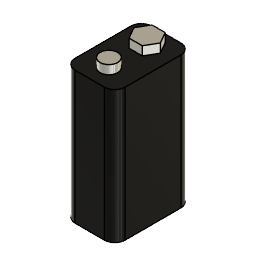
Rover (Autodesk Fusion 360 archive; units mm, degrees)
design "9V_Battery"
Autodesk Fusion 360 part; units mm, degrees
sketch "Skizze1" plane through (0, 0, 0) normal (0, 0, 1) x (1, 0, 0)
  line L0 (8.5, 13) -> (-8.5, 13)
  line L1 (-8.5, 13) -> (-8.5, -13)
  line L2 (-8.5, -13) -> (8.5, -13)
  line L3 (8.5, -13) -> (8.5, 13)
  line L4 (8.5, 13) -> (-8.5, -13) construction
  line L5 (-8.5, 13) -> (8.5, -13) construction
  dimension "d1" = 17
  dimension "d2" = 26
  constraint horizontal L0
  constraint perpendicular L0 L1
  constraint parallel L0 L2
  constraint parallel L1 L3
  constraint coincident L4 origin
  constraint coincident L5 origin
  measures "d1" distance of L0.start L0.end
  measures "d2" distance of L0.start L2.end
extrude "Extrusion1" add sketch "Skizze1" along normal blind 45
sketch "Skizze2" plane through (0, 0, 45) normal (0, 0, 1) x (-1, 0, 0)
  line L0 (-8.5, 13) -> (-8.5, -13)
  line L1 (-8.5, -13) -> (8.5, -13)
  line L2 (8.5, -13) -> (8.5, 13)
  line L3 (8.5, 13) -> (-8.5, 13)
  circle A0 centre (0, -6.5) radius 3 construction
  circle A1 centre (0, 6.5) radius 3
  line L4 (0, 0) -> (-12.8308, 0) construction
  line L5 (2.25, -10.3971) -> (-2.25, -10.3971)
  line L6 (-2.25, -10.3971) -> (-4.5, -6.5)
  line L7 (-4.5, -6.5) -> (-2.25, -2.6029)
  line L8 (-2.25, -2.6029) -> (2.25, -2.6029)
  line L9 (2.25, -2.6029) -> (4.5, -6.5)
  line L10 (4.5, -6.5) -> (2.25, -10.3971)
  circle A2 centre (0, -6.5) radius 4.5 construction
  line L11 (0, 0) -> (0, -16.3032) construction
  dimension "d5" = 13
  dimension "d6" = 6
  dimension "d7" = 9
  constraint coincident L4.start L11.start
  constraint horizontal L4
  constraint symmetric A0 A1 L4
  constraint horizontal L5
  constraint parallel L5 L8
  constraint parallel L6 L9
  constraint equal L5 L6
  constraint equal L5 L10
  constraint equal L9 L10
  constraint equal L8 L9
  constraint parallel L7 L10
  constraint coincident L5.end A2
  constraint coincident L6.end A2
  constraint coincident L7.end A2
  constraint coincident L8.end A2
  constraint coincident L9.end A2
  constraint coincident A0.centre A2.centre
  constraint perpendicular L1 L11
  constraint coincident A0.centre L11
  measures "d5" distance of A0.centre A1.centre
  measures "d6" diameter of A1
  measures "d7" distance of L6.end L9.end
extrude "Extrusion2" add sketch "Skizze2" along normal blind 3 contours A1 | L5 L6 L7 L8 L9 L10
fillet "Abrundung1" radius 3.5 4 edges at (-8.5, -13, 22.5) (-8.5, 13, 22.5) (8.5, 13, 22.5) (8.5, -13, 22.5)

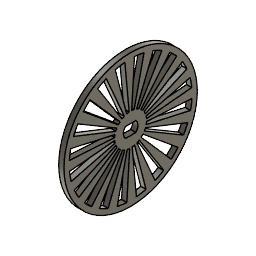
design "Encoder_Wheel_40"
Autodesk Fusion 360 part; units mm, degrees
sketch "Skizze1" plane through (0, 0, 0) normal (1, 0, 0) x (0, 1, 0)
  circle A0 centre (0, 0) radius 25
  circle A1 centre (0, 0) radius 6
  circle A2 centre (0, 0) radius 2.725
  line L0 (-1.9287, 1.925) -> (1.9287, 1.925)
  line L1 (-1.9287, -1.925) -> (1.9287, -1.925)
  line L2 (0, 0) -> (4.9, 0) construction
  circle A3 centre (0, 0) radius 23
  line L3 (-2.1738, 22.897) -> (-0.5671, 5.9731)
  line L4 (0, 0) -> (-0.5671, 5.9731) construction
  line L5 (0, 0) -> (0.5671, 5.9731) construction
  line L6 (0, 0) -> (0, 27) construction
  line L7 (-5.7289, 22.2751) -> (-1.4945, 5.8109)
  line L8 (-9.143, 21.1046) -> (-2.3851, 5.5056)
  line L9 (-12.3319, 19.4145) -> (-3.217, 5.0647)
  line L10 (-15.2172, 17.2464) -> (-3.9697, 4.4991)
  line L11 (-17.7277, 14.6536) -> (-4.6246, 3.8227)
  line L12 (-19.8018, 11.6999) -> (-5.1657, 3.0522)
  line L13 (-21.3883, 8.4582) -> (-5.5796, 2.2065)
  line L14 (-22.4481, 5.0082) -> (-5.856, 1.3065)
  line L15 (-22.9552, 1.4349) -> (-5.9883, 0.3743)
  line L16 (-22.897, -2.1738) -> (-5.9731, -0.5671)
  line L17 (-22.2751, -5.7289) -> (-5.8109, -1.4945)
  line L18 (-21.1046, -9.143) -> (-5.5056, -2.3851)
  line L19 (-19.4145, -12.3319) -> (-5.0647, -3.217)
  line L20 (-17.2464, -15.2172) -> (-4.4991, -3.9697)
  line L21 (-14.6536, -17.7277) -> (-3.8227, -4.6246)
  line L22 (-11.6999, -19.8018) -> (-3.0522, -5.1657)
  line L23 (-8.4582, -21.3883) -> (-2.2065, -5.5796)
  line L24 (-5.0082, -22.4481) -> (-1.3065, -5.856)
  line L25 (-1.4349, -22.9552) -> (-0.3743, -5.9883)
  line L26 (2.1738, -22.897) -> (0.5671, -5.9731)
  line L27 (5.7289, -22.2751) -> (1.4945, -5.8109)
  line L28 (9.143, -21.1046) -> (2.3851, -5.5056)
  line L29 (12.3319, -19.4145) -> (3.217, -5.0647)
  line L30 (15.2172, -17.2464) -> (3.9697, -4.4991)
  line L31 (17.7277, -14.6536) -> (4.6246, -3.8227)
  line L32 (19.8018, -11.6999) -> (5.1657, -3.0522)
  line L33 (21.3883, -8.4582) -> (5.5796, -2.2065)
  line L34 (22.4481, -5.0082) -> (5.856, -1.3065)
  line L35 (22.9552, -1.4349) -> (5.9883, -0.3743)
  line L36 (22.897, 2.1738) -> (5.9731, 0.5671)
  line L37 (22.2751, 5.7289) -> (5.8109, 1.4945)
  line L38 (21.1046, 9.143) -> (5.5056, 2.3851)
  line L39 (19.4145, 12.3319) -> (5.0647, 3.217)
  line L40 (17.2464, 15.2172) -> (4.4991, 3.9697)
  line L41 (14.6536, 17.7277) -> (3.8227, 4.6246)
  line L42 (11.6999, 19.8018) -> (3.0522, 5.1657)
  line L43 (8.4582, 21.3883) -> (2.2065, 5.5796)
  line L44 (5.0082, 22.4481) -> (1.3065, 5.856)
  line L45 (1.4349, 22.9552) -> (0.3743, 5.9883)
  dimension "d1" = 50
  dimension "d2" = 12
  dimension "d3" = 5.45
  dimension "d4" = 3.85
  dimension "d5" = 2
  dimension "d9" = 360
  constraint coincident A0.centre A1.centre
  constraint concentric A0 A1
  constraint concentric A1 A2
  constraint coincident A2 L0.start
  constraint coincident A2 L0.end
  constraint horizontal L0
  constraint coincident A2 L1.start
  constraint coincident A2 L1.end
  constraint parallel L0 L1
  constraint horizontal L2
  constraint symmetric L0 L1 L2
  constraint coincident A3 L3.start
  constraint coincident A1 L3.end
  constraint coincident A1 L5.end
  constraint collinear L3 L4
  constraint vertical L6
  measures "d1" diameter of A0
  measures "d2" diameter of A1
  measures "d3" diameter of A2
  measures "d4" distance of L0 L1
  measures "d5" distance of A0 A3
extrude "Extrusion1" add sketch "Skizze1" along normal blind 2 contours A0 | A1 | A2 L0 | A2 L1 makes body 1 at (2, 0.1495, -3.2777) makes body 2 at (1.3333, 24.9689, -1.2461)
extrude "Extrusion2" add sketch "Skizze1" along normal blind 2 separate body contours A1 A3 L3 L45 makes body 3
pattern_circular "C-Anordnung1" count 20 over 360 about axis through (1.75, 0, 0) along (1, 0, 0) of bodies 3 makes body 4 at (0, -6.518, 16.0548) makes body 5 at (0, -11.1602, 13.2549) makes body 6 at (0, -14.6543, 9.2462) makes body 7 at (0, -16.5788, 5.0382) makes body 8 at (0, -17.2904, -1.1333) makes body 9 at (0, -16.0548, -6.518) makes body 10 at (0, -13.2549, -11.1602) makes body 11 at (0, -9.1574, -14.71) makes body 12 at (0, -5.9973, -16.2565) makes body 13 at (0, 1.1333, -17.2904) makes body 14 at (0, 6.518, -16.0548) makes body 15 at (0, 11.1602, -13.2549) makes body 16 at (0, 14.6543, -9.2462) makes body 17 at (0, 16.5788, -5.0382) makes body 18 at (0, 17.2904, 1.1333) makes body 19 at (0, 16.0548, 6.518) makes body 20 at (0, 13.8208, 10.4512) makes body 21 at (0, 9.9147, 14.2105) makes body 22 at (0, 4.2652, 16.7943)
combine "Kombinieren1" operation add target body 2 tool bodies 14 17 4 7 20 1 19 5 11 12 8 15 21 10 13 16 22 18 3 9 6

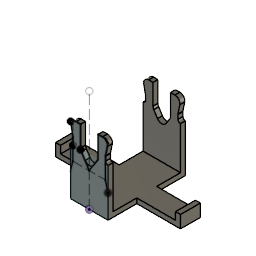
design "9V_Block_Mounting"
Autodesk Fusion 360 part; units mm, degrees
sketch "Skizze1" plane through (0, 0, 0) normal (0, 0, 1) x (1, 0, 0)
  line L0 (7.5, 13.5) -> (-7.5, 13.5)
  line L1 (-7.5, 13.5) -> (-7.5, -13.5)
  line L2 (-7.5, -13.5) -> (7.5, -13.5)
  line L3 (7.5, -13.5) -> (7.5, 13.5)
  line L4 (7.5, 13.5) -> (-7.5, -13.5) construction
  line L5 (-7.5, 13.5) -> (7.5, -13.5) construction
  line L6 (-23, 4) -> (-23, -4)
  line L7 (23, -4) -> (23, 4)
  line L8 (23, 4) -> (-23, -4) construction
  line L9 (-23, 4) -> (23, -4) construction
  line L10 (23, 4) -> (7.5, 4)
  line L11 (-7.5, 4) -> (-23, 4)
  line L12 (-23, -4) -> (-7.5, -4)
  line L13 (7.5, -4) -> (23, -4)
  line L14 (-7.5, 13.5) -> (7.5, 13.5)
  line L15 (7.5, 13.5) -> (7.5, 15.5)
  line L16 (7.5, 15.5) -> (-7.5, 15.5)
  line L17 (-7.5, 15.5) -> (-7.5, 13.5)
  line L18 (0, 0) -> (140, 0) construction
  line L19 (0, 0) -> (0, 80) construction
  line L20 (23, 4) -> (25, 4)
  line L21 (25, 4) -> (25, -4)
  line L22 (25, -4) -> (23, -4)
  line L23 (23, -4) -> (23, 4)
  line L24 (-7.5, -15.5) -> (-7.5, -13.5)
  line L25 (7.5, -15.5) -> (-7.5, -15.5)
  line L26 (7.5, -13.5) -> (7.5, -15.5)
  line L27 (-23, 4) -> (-25, 4)
  line L28 (-25, 4) -> (-25, -4)
  line L29 (-25, -4) -> (-23, -4)
  dimension "d1" = 2
  dimension "d2" = 27
  dimension "d3" = 46
  dimension "d4" = 2
  dimension "d5" = 15
  dimension "d6" = 8
  constraint horizontal L0
  constraint perpendicular L0 L1
  constraint parallel L0 L2
  constraint parallel L1 L3
  constraint coincident L4 L18.start
  constraint coincident L5 L18.start
  constraint coincident L18.start L19.start
  constraint horizontal L10
  constraint perpendicular L6 L11
  constraint parallel L10 L13
  constraint parallel L6 L7
  constraint coincident L8 L18.start
  constraint coincident L9 L18.start
  constraint coincident L1 L11.start
  constraint collinear L10 L11
  constraint coincident L3 L10.end
  constraint coincident L3 L13.start
  constraint collinear L12 L13
  constraint coincident L1 L12.end
  constraint horizontal L14
  constraint vertical L15
  constraint horizontal L16
  constraint vertical L17
  constraint perpendicular L7 L18
  constraint perpendicular L18 L19
  constraint collinear L3 L15
  constraint horizontal L20
  constraint vertical L21
  constraint horizontal L22
  constraint vertical L23
  constraint coincident L7 L8.start
  constraint coincident L10 L7.end
  constraint collinear L13 L22
  constraint symmetric L0.end L18 L1.end
  constraint symmetric L0.start L18 L2.end
  constraint symmetric L15.end L18 L25.start
  constraint symmetric L16.end L18 L24.start
  constraint symmetric L19 L7.end L6.start
  constraint symmetric L19 L20.end L27.end
  constraint symmetric L19 L21.end L28.end
  constraint symmetric L19 L7.start L6.end
  measures "d1" distance of L0.start L15.end
  measures "d2" distance of L0.start L2.end
  measures "d3" distance of L6 L7
  measures "d4" distance of L7.end L20.end
  measures "d5" distance of L0.start L0.end
  measures "d6" distance of L20.end L21.end
extrude "Extrusion1" add sketch "Skizze1" along normal blind 2 contours L0 L1 L2 L3 L14 | L3 L7 L10 L13 L23 | L1 L6 L11 L12
extrude "Extrusion2" add sketch "Skizze1" along normal blind 5 contours L7 L20 L21 L22 L23 | L6 L27 L28 L29
extrude "Extrusion3" add sketch "Skizze1" along normal blind 19 contours L0 L14 L15 L16 L17 | L2 L24 L25 L26
sketch "Skizze2" plane through (0, -15.5, 0) normal (0, -1, 0) x (1, 0, 0)
  line L0 (-7.5, 0) -> (7.5, 0)
  line L1 (7.5, 0) -> (7.5, 19)
  line L2 (7.5, 19) -> (-7.5, 19)
  line L3 (-7.5, 19) -> (-7.5, 0)
  line L4 (-7.5, 26.8) -> (-6.5, 27.8)
  line L5 (-6.5, 27.8) -> (-3.5, 27.8)
  line L6 (-3.5, 27.8) -> (-3.5, 19)
  line L7 (-6.5, 19) -> (-6.5, 27.8) construction
  line L8 (-7.5, 26.8) -> (-6.5, 21.8)
  line L9 (-6.5, 21.8) -> (-6.5, 19)
  line L10 (0, 0) -> (0, 41) construction
  line L11 (-6.5, 19) -> (-6.5, 13.5)
  line L12 (-6.5, 13.5) -> (-7.5, 9.5)
  line L13 (6.5, 13.5) -> (7.5, 9.5)
  line L14 (6.5, 19) -> (6.5, 13.5)
  line L15 (6.5, 21.8) -> (6.5, 19)
  line L16 (7.5, 26.8) -> (6.5, 21.8)
  line L17 (7.5, 26.8) -> (6.5, 27.8)
  line L18 (6.5, 27.8) -> (3.5, 27.8)
  line L19 (3.5, 27.8) -> (3.5, 19)
  line L20 (-3.5, 19) -> (0, 13.5)
  line L21 (3.5, 19) -> (0, 13.5)
  line L22 (-6.5, 13.5) -> (6.5, 13.5) construction
  dimension "d13" = 1
  dimension "d14" = 45
  dimension "d15" = 2.8
  dimension "d16" = 6
  dimension "d17" = 3
  dimension "d18" = 4
  constraint coincident L2 L7.start
  constraint coincident L2 L6.end
  constraint perpendicular L2 L6
  constraint coincident L3 L4.start
  constraint perpendicular L5 L7
  constraint perpendicular L2 L7
  constraint coincident L7 L8.end
  constraint coincident L10.start origin
  constraint perpendicular L0 L10
  constraint perpendicular L2 L11
  constraint midpoint L3 L12.end
  constraint symmetric L7.start L10 L14.start
  constraint symmetric L4.start L10 L16.start
  constraint symmetric L4.end L10 L17.end
  constraint symmetric L5.end L10 L18.end
  constraint symmetric L6.end L10 L19.end
  constraint symmetric L8.end L10 L15.start
  constraint symmetric L10 L11.end L13.start
  constraint symmetric L10 L12.end L13.end
  constraint coincident L10 L20.end
  constraint coincident L20.end L22
  measures "d13" distance of L2.end L7.start
  measures "d14" angle of L4 L7
  measures "d15" distance of L2 L8.end
  measures "d16" distance of L4.end L8.end
  measures "d17" distance of L4.end L5.end
  measures "d18" distance of L12.end L22
extrude "Extrusion4" add sketch "Skizze2" against normal up to surface (31 mm away) contours L2 L4 L5 L6 L8 L9 | L2 L15 L16 L17 L18 L19
extrude "Extrusion5" cut sketch "Skizze2" against normal up to surface (31 mm away) contours L2 L20 L21
extrude "Extrusion6" cut 1 faces at (2.5, -10.3333, 2) along direction (0, 0, 1) up to surface (25.8 mm away)
fillet "Abrundung1" radius 1 8 edges at (-6.5, -14.5, 19) (6.5, -14.5, 19) (6.5, 14.5, 19) (-6.5, 14.5, 19) (6.5, -14.5, 21.8) (-6.5, -14.5, 21.8) (6.5, 14.5, 21.8) (-6.5, 14.5, 21.8)
fillet "Abrundung1" radius 1 4 edges at (6.5, -14.5, 27.8) (6.5, 14.5, 27.8) (-6.5, -14.5, 27.8) (-6.5, 14.5, 27.8)
fillet "Abrundung2" radius 2 4 edges at (-7.5, 14.5, 26.8) (-7.5, -14.5, 26.8) (7.5, 14.5, 26.8) (7.5, -14.5, 26.8)
fillet "Abrundung3" radius 2 6 edges at (3.5, -14.5, 19) (-3.5, -14.5, 19) (-3.5, 14.5, 19) (3.5, 14.5, 19) (0, 14.5, 13.5) (0, -14.5, 13.5)
equation "d9 = 2 mm + 3 mm"
equation "d11 = 2 mm + 17 mm"

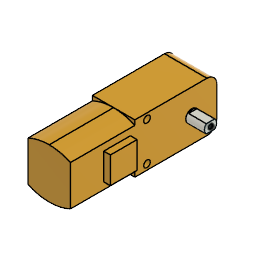
design "Yellow_Motor"
Autodesk Fusion 360 part; units mm, degrees
sketch "Skizze1" plane through (0, 0, 0) normal (1, 0, 0) x (0, 1, 0) in component "Housing"
  line L0 (-1.8875, 2) -> (1.8875, 2)
  line L1 (-1.8875, -2) -> (1.8875, -2)
  circle A0 centre (0, 0) radius 2.75
  line L2 (-25.7, 11.2) -> (11.3, 11.2)
  line L3 (11.3, 11.2) -> (11.3, -11.2)
  line L4 (11.3, -11.2) -> (-25.7, -11.2)
  line L5 (-25.7, -11.2) -> (-25.7, 11.2)
  line L6 (0, 0) -> (23, 0) construction
  dimension "d1" = 5.5
  dimension "d2" = 4
  dimension "d3" = 11.3
  dimension "d4" = 22.4
  dimension "d5" = 37
  constraint coincident A0.centre L6.start
  constraint coincident L0.start A0
  constraint coincident L0.end A0
  constraint horizontal L0
  constraint coincident L1.start A0
  constraint coincident L1.end A0
  constraint parallel L0 L1
  constraint horizontal L2
  constraint vertical L3
  constraint horizontal L4
  constraint vertical L5
  constraint perpendicular L3 L6
  constraint symmetric L0 L1 L6
  constraint symmetric L2 L4 L6
  measures "d1" diameter of A0
  measures "d2" distance of L0 L1
  measures "d3" distance of A0.centre L3
  measures "d4" distance of L2.end L3.end
  measures "d5" distance of L2.start L2.end
extrude "Extrusion1" add sketch "Skizze1" along normal blind 9.575 and the other way blind 9.575 makes body 1 in component "Housing"
sketch "Skizze2" plane through (0, -25.7, 0) normal (0, -1, 0) x (1, 0, 0) in component "Housing"
  line L0 (-9.575, -11.2) -> (9.575, -11.2)
  line L1 (9.575, -11.2) -> (9.575, 11.2)
  line L2 (9.575, 11.2) -> (-9.575, 11.2)
  line L3 (-9.575, 11.2) -> (-9.575, -11.2)
  arc A0 (9.575, 9.054) -> (0, 11.2) centre (0, -11.234) ccw
  line L4 (0, 0) -> (0, 18.4987) construction
  line L5 (0, 0) -> (15, 0) construction
  arc A1 (0, 11.2) -> (-9.575, 9.054) centre (0, -11.234) ccw
  arc A2 (-9.575, -9.054) -> (0, -11.2) centre (0, 11.234) ccw
  arc A3 (0, -11.2) -> (9.575, -9.054) centre (0, 11.234) ccw
  constraint coincident L1 A0.start
  constraint midpoint L2 A0.end
  constraint coincident L4.start L5.start
  constraint perpendicular L2 L4
  constraint perpendicular L4 L5
  constraint symmetric A0.end L4 A1.start
  constraint symmetric A0.start L4 A1.end
  constraint symmetric A0 L4 A1
  constraint tangent L2 A0
  constraint symmetric A0.end L5 A2.end
  constraint symmetric A0.start L5 A3.end
  constraint symmetric A0 L5 A3
  constraint symmetric L5 A1.end A2.start
  constraint symmetric L5 A0.end A2.end
  constraint symmetric L5 A1 A2
extrude "Extrusion2" add sketch "Skizze2" along normal blind 29 contours L1 L3 A0 A1 A2 A3 bodies 1 in component "Housing"
sketch "Skizze3" plane through (9.575, 0, 0) normal (1, 0, 0) x (0, 1, 0) in component "Housing"
  circle A0 centre (0, 0) radius 2.75
  line L0 (-25.7, -11.2) -> (11.3, -11.2)
  line L1 (11.3, -11.2) -> (11.3, 11.2)
  line L2 (11.3, 11.2) -> (-25.7, 11.2)
  line L3 (-25.7, 11.2) -> (-25.7, 9.054)
  line L4 (-25.7, 9.054) -> (-54.7, 9.054)
  line L5 (-54.7, 9.054) -> (-54.7, -9.054)
  line L6 (-54.7, -9.054) -> (-25.7, -9.054)
  line L7 (-25.7, -9.054) -> (-25.7, -11.2)
  line L8 (-39.7, 6) -> (-27.7, 6)
  line L9 (-27.7, 6) -> (-27.7, -6)
  line L10 (-27.7, -6) -> (-39.7, -6)
  line L11 (-39.7, -6) -> (-39.7, 6)
  line L12 (0, 0) -> (-65, 0) construction
  dimension "d12" = 14
  dimension "d14" = 12
  dimension "d15" = 2
  constraint horizontal L8
  constraint vertical L9
  constraint horizontal L10
  constraint vertical L11
  constraint coincident A0.centre L12.start
  constraint horizontal L12
  constraint symmetric L8 L10 L12
  measures "d12" distance of L3 L11
  measures "d14" distance of L8.end L9.end
  measures "d15" distance of L3 L9
extrude "Extrusion3" add sketch "Skizze3" along normal blind 3 and the other way up to surface (22.15 mm away) contours L8 L9 L10 L11 bodies 1 in component "Housing"
sketch "Skizze4" plane through (9.575, 0, 0) normal (1, 0, 0) x (0, 1, 0) in component "Housing"
  line L0 (-39.7, -6) -> (-39.7, 6)
  line L1 (-39.7, 6) -> (-27.7, 6)
  line L2 (-27.7, 6) -> (-27.7, -6)
  line L3 (-27.7, -6) -> (-39.7, -6)
  circle A0 centre (0, 0) radius 2.75
  line L4 (-25.7, -11.2) -> (11.3, -11.2)
  line L5 (11.3, -11.2) -> (11.3, 11.2)
  line L6 (11.3, 11.2) -> (-25.7, 11.2)
  line L7 (-25.7, 11.2) -> (-25.7, 9.054)
  line L8 (-25.7, 9.054) -> (-54.7, 9.054)
  line L9 (-54.7, 9.054) -> (-54.7, -9.054)
  line L10 (-54.7, -9.054) -> (-25.7, -9.054)
  line L11 (-25.7, -9.054) -> (-25.7, -11.2)
  circle A1 centre (-20.2, 8.7) radius 1.5
  line L12 (0, 0) -> (17, 0) construction
  circle A2 centre (-20.2, -8.7) radius 1.5
  dimension "d20" = 3
  dimension "d21" = 1
  dimension "d22" = 30
  constraint coincident A0.centre L12.start
  constraint perpendicular L5 L12
  constraint symmetric A1 L12 A2
  measures "d20" diameter of A1
  measures "d21" distance of L6 A1
  measures "d22" distance of L5 A1
extrude "Extrusion4" cut sketch "Skizze4" against normal up to surface (19.15 mm away) contours A1 | A2 bodies 1 in component "Housing"
sketch "Skizze5" plane through (0, 11.3, 0) normal (0, 1, 0) x (-1, 0, 0) in component "Housing"
  line L0 (9.575, 11.2) -> (-9.575, 11.2)
  line L1 (-9.575, 11.2) -> (-9.575, -11.2)
  line L2 (-9.575, -11.2) -> (9.575, -11.2)
  line L3 (9.575, -11.2) -> (9.575, 11.2)
  line L4 (-2.475, 2.6) -> (0.675, 2.6)
  line L5 (0.675, 2.6) -> (0.675, -2.6)
  line L6 (0.675, -2.6) -> (-2.475, -2.6)
  line L7 (-2.475, -2.6) -> (-2.475, 2.6)
  line L8 (0, 0) -> (7, 0) construction
  dimension "d25" = 5.2
  dimension "d27" = 7.1
  dimension "d55" = 8.9
  constraint horizontal L4
  constraint vertical L5
  constraint horizontal L6
  constraint vertical L7
  constraint coincident L8.start origin
  constraint perpendicular L5 L8
  constraint symmetric L4 L6 L8
  measures "d25" distance of L4.end L5.end
  measures "d27" distance of L1 L7
  measures "d55" distance of L3 L5
extrude "Extrusion5" add sketch "Skizze5" along normal blind 5 contours L4 L5 L6 L7 bodies 1 in component "Housing"
sketch "Skizze6" plane through (2.475, 0, 0) normal (1, 0, 0) x (0, 1, 0) in component "Housing"
  line L0 (11.3, 2.6) -> (11.3, -2.6)
  line L1 (11.3, -2.6) -> (16.3, -2.6)
  line L2 (16.3, -2.6) -> (16.3, 2.6)
  line L3 (16.3, 2.6) -> (11.3, 2.6)
  circle A0 centre (13.8, 0) radius 1.5
  line L4 (11.3, 2.6) -> (16.3, -2.6) construction
  line L5 (16.3, 2.6) -> (11.3, -2.6) construction
  dimension "d30" = 3
  constraint coincident L0.start L3.end
  constraint coincident L1.end L2.start
  constraint coincident L2.end L3.start
  constraint coincident L0.end L1.start
  constraint coincident A0.centre L5
  constraint coincident A0.centre L4
  measures "d30" diameter of A0
extrude "Extrusion6" cut sketch "Skizze6" against normal up to surface (3.15 mm away) contours A0 bodies 1 in component "Housing"
fillet "Abrundung1" radius 0.5 4 edges at (0.9, 11.3, 2.6) (2.475, 11.3, 0) (0.9, 11.3, -2.6) (-0.675, 11.3, 0) on bodies 1 in component "Housing"
fillet "Abrundung2" radius 4.5 2 edges at (0, 11.3, 11.2) (0, 11.3, -11.2) on bodies 1 in component "Housing"
sketch "Skizze7" plane through (-9.575, 0, 0) normal (-1, 0, 0) x (0, -1, 0) in component "Housing"
  circle A0 centre (20.2, 8.7) radius 1.5
  circle A1 centre (20.2, -8.7) radius 1.5
  line L0 (39.7, 6) -> (39.7, -6)
  line L1 (39.7, -6) -> (27.7, -6)
  line L2 (27.7, -6) -> (27.7, 6)
  line L3 (27.7, 6) -> (39.7, 6)
  circle A2 centre (0, 0) radius 2.75
  arc A3 (-11.3, -6.7) -> (-6.8, -11.2) centre (-6.8, -6.7) ccw
  line L4 (-6.8, -11.2) -> (25.7, -11.2)
  line L5 (25.7, -11.2) -> (25.7, -9.054)
  line L6 (25.7, -9.054) -> (54.7, -9.054)
  line L7 (54.7, -9.054) -> (54.7, 9.054)
  line L8 (54.7, 9.054) -> (25.7, 9.054)
  line L9 (25.7, 9.054) -> (25.7, 11.2)
  line L10 (25.7, 11.2) -> (-6.8, 11.2)
  arc A4 (-6.8, 11.2) -> (-11.3, 6.7) centre (-6.8, 6.7) ccw
  line L11 (-11.3, 6.7) -> (-11.3, -6.7)
  circle A5 centre (10.9, 0) radius 2
  line L12 (0, 0) -> (25, 0) construction
  dimension "d37" = 4
  dimension "d38" = 22.2
  constraint coincident A2.centre L12.start
  constraint perpendicular L2 L12
  constraint coincident A5.centre L12
  measures "d37" diameter of A5
  measures "d38" distance of L11 A5.centre
extrude "Extrusion7" add sketch "Skizze7" along normal blind 2 contours A5 bodies 1 in component "Housing"
extrude "Extrusion1'" add sketch "Skizze1" along normal mid plane 20 separate body contours L0 A0 | L0 L1 A0 | L1 A0 makes body 2 in component "Axis"
extrude "Extrusion2'" add sketch "Skizze1" along normal mid plane 36 contours L0 L1 A0 bodies 2 in component "Axis"
sketch "Skizze1 (2)" plane through (18, 0, 0) normal (1, 0, 0) x (0, 1, 0) in component "Axis"
  arc A0 (-1.8875, 2) -> (-1.8875, -2) centre (0, 0) ccw
  line L0 (-1.8875, -2) -> (1.8875, -2)
  arc A1 (1.8875, -2) -> (1.8875, 2) centre (0, 0) ccw
  line L1 (1.8875, 2) -> (-1.8875, 2)
  circle A2 centre (0, 0) radius 0.85
  dimension "d45" = 1.7
  constraint concentric A0 A2
  measures "d45" diameter of A2
extrude "Extrusion3'" cut sketch "Skizze1 (2)" against normal up to surface (8 mm away) contours A2 bodies 2 in component "Axis"
extrude "Extrusion4'" cut sketch "Skizze1 (2)" along normal up to surface (8 mm away) from surface at -36 contours A2 bodies 2 in component "Axis"
component "Housing" placed x (1, 0, 0) y (0, 1, 0) z (0, 0, 1) at (0, 0, 0)
component "Axis" placed x (1, 0, 0) y (0, 1, 0) z (0, 0, 1) at (0, 0, 0)
equation "d6 = ( 19.15 / 2 ) * 1 mm"
equation "d8 = ( 19.15 / 2 ) * 1 mm"
equation "d38 = 24.2 mm - 2 mm"
equation "d43 = ( 36 / 2 ) * 1 mm"

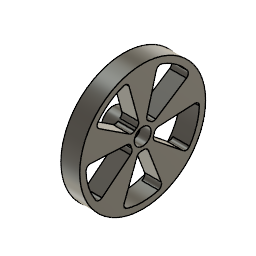
design "Wheel"
Autodesk Fusion 360 part; units mm, degrees
sketch "Skizze1" plane through (0, 0, 0) normal (1, 0, 0) x (0, 1, 0)
  circle A0 centre (0, 0) radius 2.725
  line L0 (-1.9287, 1.925) -> (1.9287, 1.925)
  line L1 (1.9287, -1.925) -> (-1.9287, -1.925)
  circle A1 centre (0, 0) radius 30
  dimension "d1" = 5.45
  dimension "d2" = 3.85
  dimension "d3" = 60
  constraint coincident A0.centre A1.centre
  constraint coincident A0 L0.start
  constraint coincident A0 L0.end
  constraint coincident A0 L1.start
  constraint coincident A0 L1.end
  constraint parallel L0 L1
  constraint equal L0 L1
  constraint horizontal L0
  constraint concentric A0 A1
  measures "d1" diameter of A0
  measures "d2" distance of L0 L1
  measures "d3" diameter of A1
extrude "Extrusion1" add sketch "Skizze1" along normal blind 7 contours A0 L0 | A0 L1 | A1
sketch "Skizze2" plane through (7, 0, 0) normal (1, 0, 0) x (0, 1, 0)
  arc A0 (-1.9287, 1.925) -> (-1.9287, -1.925) centre (0, 0) ccw
  line L0 (-1.9287, 1.925) -> (1.9287, 1.925)
  arc A1 (1.9287, -1.925) -> (1.9287, 1.925) centre (0, 0) ccw
  line L1 (1.9287, -1.925) -> (-1.9287, -1.925)
  circle A2 centre (0, 0) radius 30
  circle A3 centre (0, 0) radius 1.75
  dimension "d6" = 3.5
  constraint concentric A0 A3
  measures "d6" diameter of A3
extrude "Extrusion2" add sketch "Skizze2" along normal blind 2 contours A0 L0 A1 L1 | A2
sketch "Skizze3" plane through (0, 0, 0) normal (-1, 0, 0) x (0, -1, 0)
  arc A0 (1.9287, -1.925) -> (1.9287, 1.925) centre (0, 0) ccw
  line L0 (1.9287, -1.925) -> (-1.9287, -1.925)
  arc A1 (-1.9287, 1.925) -> (-1.9287, -1.925) centre (0, 0) ccw
  line L1 (-1.9287, 1.925) -> (1.9287, 1.925)
  circle A2 centre (0, 0) radius 30
  circle A3 centre (0, 0) radius 5.725
  circle A4 centre (0, 0) radius 27
  line L2 (-7.0742, 26.0568) -> (-1.5, 5.525)
  line L3 (7.0742, 26.0568) -> (1.5, 5.525)
  line L4 (0, 5.725) -> (0, 27) construction
  line L5 (0, 10.5624) -> (2.6708, 9.8373) construction
  line L6 (0, 10.5624) -> (-2.6708, 9.8373) construction
  line L7 (0, 0) -> (32, 0) construction
  line L8 (-26.9675, 1.324) -> (-5.7181, 0.2807)
  line L9 (-22.5954, 14.78) -> (-4.7911, 3.1339)
  line L10 (-9.5926, -25.2385) -> (-2.034, -5.3515)
  line L11 (-21.039, -16.9222) -> (-4.461, -3.5881)
  line L12 (21.039, -16.9222) -> (4.461, -3.5881)
  line L13 (9.5926, -25.2385) -> (2.034, -5.3515)
  line L14 (22.5954, 14.78) -> (4.7911, 3.1339)
  line L15 (26.9675, 1.324) -> (5.7181, 0.2807)
  dimension "d9" = 3
  dimension "d10" = 3
  dimension "d11" = 3
  dimension "d13" = 360
  constraint concentric A0 A3
  constraint concentric A0 A4
  constraint coincident A4 L2.start
  constraint coincident A3 L2.end
  constraint coincident A4 L3.start
  constraint coincident A3 L3.end
  constraint coincident A3 L4.start
  constraint coincident A4 L4.end
  constraint coincident A0.centre L3
  constraint coincident A0.centre L2
  constraint coincident A0.centre L4
  constraint coincident L4 L5.start
  constraint coincident L3 L5.end
  constraint perpendicular L3 L5
  constraint coincident L2 L6.end
  constraint perpendicular L2 L6
  constraint equal L5 L6
  constraint coincident A0.centre A1.centre
  constraint horizontal L7
  constraint perpendicular L4 L7
  measures "d9" distance of A0 A3
  measures "d10" distance of A2 A4
  measures "d11" horizontal distance of L2.end L3.end
extrude "Extrusion3" cut sketch "Skizze3" against normal up to surface (9 mm away) contours A3 A4 L12 L15 | A3 A4 L3 L14 | A3 A4 L10 L13 | A3 A4 L2 L9 | A3 A4 L8 L11
sketch "Skizze4" plane through (0, 0, 0) normal (-1, 0, 0) x (0, -1, 0)
  line L0 (-9.5926, -25.2385) -> (-2.034, -5.3515)
  arc A0 (-2.034, -5.3515) -> (2.034, -5.3515) centre (0, 0) ccw
  line L1 (2.034, -5.3515) -> (9.5926, -25.2385)
  arc A1 (-9.5926, -25.2385) -> (9.5926, -25.2385) centre (0, 0) ccw
  line L2 (21.039, -16.9222) -> (4.461, -3.5881)
  arc A2 (4.461, -3.5881) -> (5.7181, 0.2807) centre (0, 0) ccw
  line L3 (5.7181, 0.2807) -> (26.9675, 1.324)
  arc A3 (21.039, -16.9222) -> (26.9675, 1.324) centre (0, 0) ccw
  line L4 (-26.9675, 1.324) -> (-5.7181, 0.2807)
  arc A4 (-5.7181, 0.2807) -> (-4.461, -3.5881) centre (0, 0) ccw
  line L5 (-4.461, -3.5881) -> (-21.039, -16.9222)
  arc A5 (-26.9675, 1.324) -> (-21.039, -16.9222) centre (0, 0) ccw
  arc A6 (22.5954, 14.78) -> (7.0742, 26.0568) centre (0, 0) ccw
  line L6 (22.5954, 14.78) -> (4.7911, 3.1339)
  arc A7 (4.7911, 3.1339) -> (1.5, 5.525) centre (0, 0) ccw
  line L7 (1.5, 5.525) -> (7.0742, 26.0568)
  line L8 (-7.0742, 26.0568) -> (-1.5, 5.525)
  arc A8 (-1.5, 5.525) -> (-4.7911, 3.1339) centre (0, 0) ccw
  line L9 (-4.7911, 3.1339) -> (-22.5954, 14.78)
  arc A9 (-7.0742, 26.0568) -> (-22.5954, 14.78) centre (0, 0) ccw
  arc A10 (1.9287, -1.925) -> (1.9287, 1.925) centre (0, 0) ccw
  line L10 (1.9287, -1.925) -> (-1.9287, -1.925)
  arc A11 (-1.9287, 1.925) -> (-1.9287, -1.925) centre (0, 0) ccw
  line L11 (-1.9287, 1.925) -> (1.9287, 1.925)
  circle A12 centre (0, 0) radius 30
  circle A13 centre (0, 0) radius 27
  circle A14 centre (0, 0) radius 5.725
  constraint concentric A0 A13
  constraint coincident A0.centre A1.centre
  constraint equal A7 A14
  constraint equal A6 A13
extrude "Extrusion4" cut sketch "Skizze4" against normal blind 1 contours L0 L5 A13 A14 | L1 L2 A13 A14 | L4 L9 A13 A14 | L3 L6 A13 A14 | L7 L8 A13 A14
fillet "Abrundung1" radius 2 10 edges at (4.5, -1.5, 5.525) (4.5, -4.7911, 3.1339) (4.5, -5.7181, 0.2807) (4.5, -4.461, -3.5881) (4.5, -2.034, -5.3515) (4.5, 2.034, -5.3515) (4.5, 4.461, -3.5881) (4.5, 5.7181, 0.2807) (4.5, 4.7911, 3.1339) (4.5, 1.5, 5.525)
fillet "Abrundung2" radius 2 10 edges at (4.5, -7.0742, 26.0568) (4.5, -22.5954, 14.78) (4.5, -26.9675, 1.324) (4.5, -21.039, -16.9222) (4.5, -9.5926, -25.2385) (4.5, 9.5926, -25.2385) (4.5, 21.039, -16.9222) (4.5, 26.9675, 1.324) (4.5, 22.5954, 14.78) (4.5, 7.0742, 26.0568)
extrude "Extrusion5" add 1 faces at (0, -0.0491, 3.191) along direction (-1, 0, 0) blind 5
fillet "Abrundung3" radius 1 4 edges at (-5, 2.725, 0) (-5, 0, 1.925) (-5, -2.725, 0) (-5, 0, -1.925)
extrude "Extrusion6" add 1 faces at (7, 2.3954, 0) along direction (-1, 0, 0) blind 5
sketch "Skizze5" plane through (9, 0, 0) normal (1, 0, 0) x (0, 1, 0)
  line L0 (2.651, -6.9748) -> (8.8536, -23.2941)
  arc A0 (7.5428, -25.925) -> (8.8536, -23.2941) centre (6.9841, -24.0046) ccw
  arc A1 (-7.5428, -25.925) -> (7.5428, -25.925) centre (0, 0) ccw
  arc A2 (-8.8536, -23.2941) -> (-7.5428, -25.925) centre (-6.9841, -24.0046) ccw
  line L1 (-8.8536, -23.2941) -> (-2.651, -6.9748)
  arc A3 (-0.5791, -5.6956) -> (-2.651, -6.9748) centre (-0.7815, -7.6854) ccw
  arc A4 (-0.5791, -5.6956) -> (0.5791, -5.6956) centre (0, 0) ccw
  arc A5 (2.651, -6.9748) -> (0.5791, -5.6956) centre (0.7815, -7.6854) ccw
  line L2 (-5.8142, -4.6766) -> (-19.4181, -15.6185)
  arc A6 (-22.3253, -15.1849) -> (-19.4181, -15.6185) centre (-20.6716, -14.0601) ccw
  arc A7 (-26.987, -0.8377) -> (-22.3253, -15.1849) centre (0, 0) ccw
  arc A8 (-24.8899, 1.222) -> (-26.987, -0.8377) centre (-24.988, -0.7756) ccw
  line L3 (-24.8899, 1.222) -> (-7.4526, 0.3659)
  arc A9 (-5.5958, -1.2093) -> (-7.4526, 0.3659) centre (-7.5507, -1.6317) ccw
  arc A10 (-5.5958, -1.2093) -> (-5.2379, -2.3108) centre (0, 0) ccw
  arc A11 (-5.8142, -4.6766) -> (-5.2379, -2.3108) centre (-7.0677, -3.1181) ccw
  line L4 (7.4526, 0.3659) -> (24.8899, 1.222)
  arc A12 (26.987, -0.8377) -> (24.8899, 1.222) centre (24.988, -0.7756) ccw
  arc A13 (22.3253, -15.1849) -> (26.987, -0.8377) centre (0, 0) ccw
  arc A14 (19.4181, -15.6185) -> (22.3253, -15.1849) centre (20.6716, -14.0601) ccw
  line L5 (19.4181, -15.6185) -> (5.8142, -4.6766)
  arc A15 (5.2379, -2.3108) -> (5.8142, -4.6766) centre (7.0677, -3.1181) ccw
  arc A16 (5.2379, -2.3108) -> (5.5958, -1.2093) centre (0, 0) ccw
  arc A17 (7.4526, 0.3659) -> (5.5958, -1.2093) centre (7.5507, -1.6317) ccw
  arc A18 (-9.1361, 25.4073) -> (-21.3406, 16.5402) centre (0, 0) ccw
  arc A19 (-6.5292, 24.0493) -> (-9.1361, 25.4073) centre (-8.4594, 23.5253) ccw
  line L6 (-6.5292, 24.0493) -> (-1.955, 7.2009)
  arc A20 (-2.8793, 4.9483) -> (-1.955, 7.2009) centre (-3.8851, 6.6769) ccw
  arc A21 (-2.8793, 4.9483) -> (-3.8163, 4.2675) centre (0, 0) ccw
  arc A22 (-6.2444, 4.0845) -> (-3.8163, 4.2675) centre (-5.1496, 5.7583) ccw
  line L7 (-6.2444, 4.0845) -> (-20.8546, 13.6413)
  arc A23 (-21.3406, 16.5402) -> (-20.8546, 13.6413) centre (-19.7598, 15.315) ccw
  line L8 (1.955, 7.2009) -> (6.5292, 24.0493)
  arc A24 (9.1361, 25.4073) -> (6.5292, 24.0493) centre (8.4594, 23.5253) ccw
  arc A25 (21.3406, 16.5402) -> (9.1361, 25.4073) centre (0, 0) ccw
  arc A26 (20.8546, 13.6413) -> (21.3406, 16.5402) centre (19.7598, 15.315) ccw
  line L9 (20.8546, 13.6413) -> (6.2444, 4.0845)
  arc A27 (3.8163, 4.2675) -> (6.2444, 4.0845) centre (5.1496, 5.7583) ccw
  arc A28 (3.8163, 4.2675) -> (2.8793, 4.9483) centre (0, 0) ccw
  arc A29 (1.955, 7.2009) -> (2.8793, 4.9483) centre (3.8851, 6.6769) ccw
  circle A30 centre (0, 0) radius 1.75
  circle A31 centre (0, 0) radius 30
  circle A32 centre (0, 0) radius 4
  dimension "d28" = 8
  constraint concentric A1 A32
  measures "d28" diameter of A32
extrude "Extrusion7" cut sketch "Skizze5" against normal blind 5 contours A32
